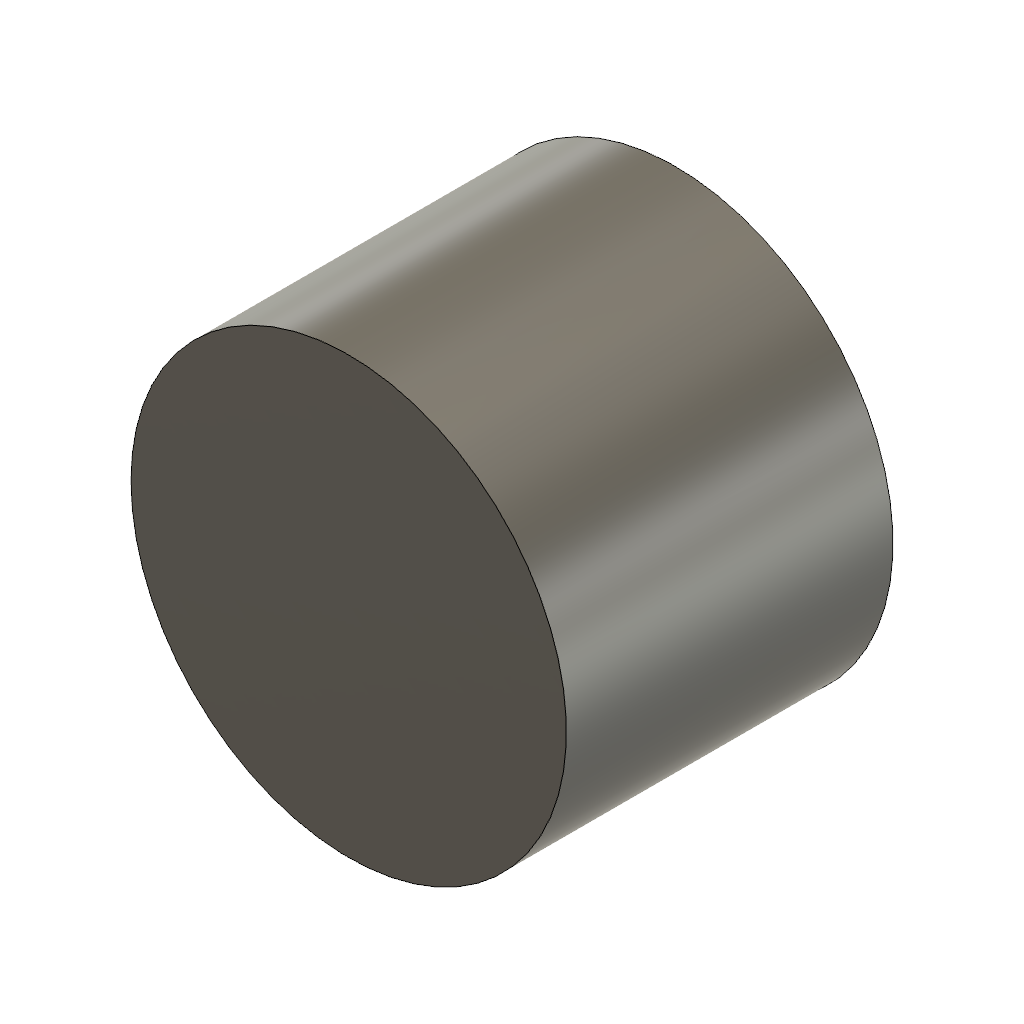
cut (Autodesk Fusion 360 design; units mm, degrees)
part number: 2026-10-20-17-27-17-414
Autodesk Fusion 360 part; units mm, degrees
sketch "BaseProfile" plane through (0, 0, 0) normal (0, 0, 1) x (1, 0, 0)
  circle A0 centre (0, 0) radius 20
extrude "BaseExtrusion" add sketch "BaseProfile" along normal blind 30
sketch "ProbeProfile" plane through (0, 0, 0) normal (0, 0, 1) x (1, 0, 0)
  circle A0 centre (0, 0) radius 10
extrude "ProbeExtrusion" cut sketch "ProbeProfile" along normal blind 17
